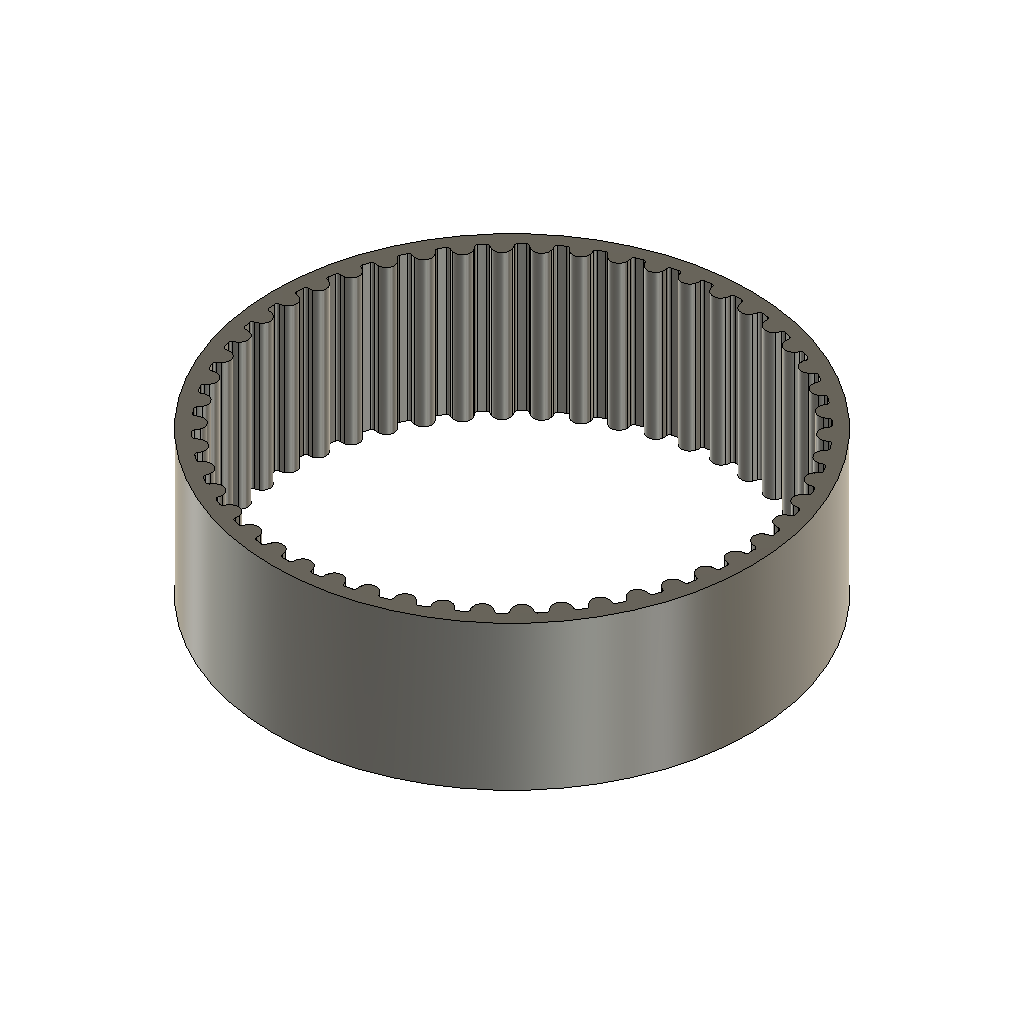
GT2-3M Belt Print (Autodesk Fusion 360 design; units mm, degrees)
Autodesk Fusion 360 part; units mm, degrees
sketch "Teeth" plane through (0, 0, 0) normal (0, 0, 1) x (1, 0, 0)
  circle A0 centre (0, 0) radius 23.8733
  arc A1 (0.6625, 22.8542) -> (1.4035, 22.3082) centre (1.4569, 23.1565) ccw
  line L0 (0, 0) -> (0, 7.1835) construction
  line L1 (0, 0) -> (1.4569, 23.1565) construction
  line L2 (0, 23.4923) -> (0, 23.8733)
  arc A2 (1.499, 23.8262) -> (0, 23.8733) centre (0, 0) ccw
  arc A3 (0.3233, 23.49) -> (0, 23.4923) centre (0, 0) ccw
  arc A4 (0.5689, 23.2619) -> (0.3233, 23.49) centre (0.3199, 23.2401) ccw
  arc A5 (0.5689, 23.2619) -> (0.6625, 22.8542) centre (2.0831, 23.3948) ccw
  line L3 (1.499, 23.8262) -> (2.1078, 23.7879) construction
  line L4 (2.0831, 23.3948) -> (2.1078, 23.7879) construction
  arc A6 (1.4035, 22.3082) -> (2.2072, 22.757) centre (1.4569, 23.1565) ccw
  arc A7 (2.2072, 22.757) -> (2.3511, 23.1498) centre (0.8655, 23.4714) ccw
  arc A8 (2.6233, 23.3453) -> (2.3511, 23.1498) centre (2.5954, 23.0969) ccw
  arc A9 (2.9444, 23.307) -> (2.6233, 23.3453) centre (0, 0) ccw
  line L5 (2.9444, 23.307) -> (2.9921, 23.685)
  arc A10 (2.9921, 23.685) -> (1.499, 23.8262) centre (0, 0) ccw
  circle A11 centre (0, 0) radius 24.7523
  dimension "d50" = 47.7465
  dimension "d59" = 3.6
  dimension "d67" = 0.381
  dimension "d68" = 0.25
  dimension "d69" = 1.521
  dimension "d71" = 0.61
  dimension "d72" = 0.85
  dimension "d73" = 1.52
  dimension "d74" = 49.5045
  constraint coincident A0.centre L0.start
  constraint coincident A0 L2.end
  constraint parallel L0 L2
  constraint coincident A0 A2.start
  constraint collinear A1.centre A0.centre A2.start
  constraint coincident A1.centre L1.end
  constraint coincident L1 A1.end
  constraint vertical L0
  constraint coincident L0 L2.start
  constraint tangent A3 A4
  constraint tangent A4 A5
  constraint tangent A1 A5
  constraint tangent A0 L3
  constraint coincident A5.centre L4.start
  constraint coincident L3 L4.end
  constraint perpendicular L3 L4
  constraint coincident L3.end L4.end
  constraint symmetric A1 L1 A6
  constraint symmetric L1 L2.end L5.end
  constraint symmetric L1 A2.start L3.start
  constraint symmetric L1 A2 A10
  constraint symmetric L1 A1.end A6.start
  constraint symmetric L1 L2.start A9.start
  constraint symmetric L1 A3.start A8.start
  constraint symmetric L1 A3 A9
  constraint symmetric L1 A4.start A7.end
  constraint symmetric L1 A4 A8
  constraint symmetric L1 A1.start A6.end
  constraint symmetric L1 A5 A7
  constraint concentric A10 A11
  measures "d50" diameter of A0
  measures "d59" angle of L0 L1
  measures "d67" distance of L2.end L2.start
  measures "d68" radius of A4
  measures "d69" distance of A2.start A1.end
  measures "d71" distance of A2.start L3.end
  measures "d72" radius of A1
  measures "d73" radius of A5
  measures "d74" diameter of A11
extrude "Extrude1" add sketch "Teeth" along normal mid plane 15
extrude "Extrude3" add sketch "Teeth" along normal through all of body 1 and the other way through all of body 1 contours A0 A1 L2 A2 A3 A4 A5 A6 A7 A8 A9 L5 A10
pattern_circular "C-Pattern1" count 50 over 360 about axis through (0, 0, 0) along (0, 0, 1) of "Extrude3"
equation "p = 3 mm"
equation "n = 50" comment "Number of Teeth"
equation "PD = n * p / 3.14159"
equation "d25 = width"
equation "d50 = PD"
equation "d52 = n"
equation "d59 = ( 180 / n ) * 1 deg"
equation "width = 15 mm"
equation "d74 = d50 + ( 2 * 0.879 mm )"
